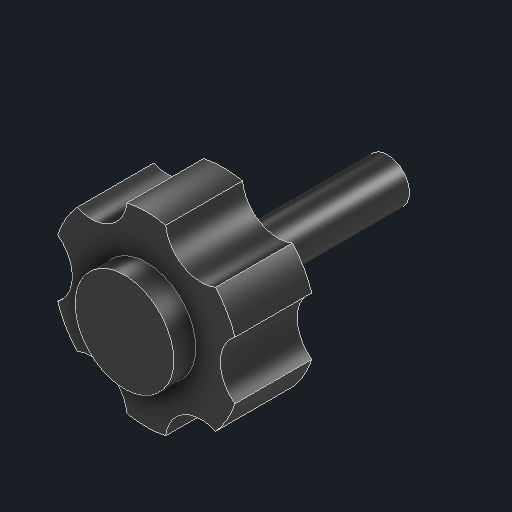
# Autodesk Inventor part: saddle_star_knob
Saved by Autodesk Inventor 2027.1 (Build 311270010, 270A)
## iProperties
Created: 2026-11-04
Part Number: saddle_star_knob
Material: Generic
Description: Saddle clamp knob
Document SubType Name: Modeling
Designer: Claude (from photos)
Density: 1 g/cm^3
Appearance: Glossy - Black
Author: alexg
Autodesk Inventor part; units mm, degrees
ref_plane "Work Plane1" through (0, 0, -18) normal (0, 0, 1) x (1, 0, 0)
sketch "Clamp screw sketch" plane through (0, 0, -18) normal (0, 0, 1) x (1, 0, 0)
  circle A0 centre (0, 0) radius 4
  constraints: 1 centre point
extrude "Clamp screw" add sketch "Clamp screw sketch" along normal blind 32
ref_plane "Work Plane2" through (0, 0, 12) normal (0, 0, 1) x (1, 0, 0)
sketch "Star body sketch" plane through (0, 0, 12) normal (0, 0, 1) x (1, 0, 0)
  circle A0 centre (0, 0) radius 17
  constraints: 1 centre point
extrude "Star body" add sketch "Star body sketch" along normal blind 14
ref_plane "Work Plane3" through (0, 0, 26) normal (0, 0, 1) x (1, 0, 0)
sketch "Lobes sketch" plane through (0, 0, 26) normal (0, 0, 1) x (1, 0, 0)
  circle A0 centre (20, 0) radius 6.5
  circle A1 centre (10, 17.3205) radius 6.5
  circle A2 centre (-10, 17.3205) radius 6.5
  circle A3 centre (-20, 0) radius 6.5
  circle A4 centre (-10, -17.3205) radius 6.5
  circle A5 centre (10, -17.3205) radius 6.5
  constraints: 6 centre point
extrude "Lobes" cut sketch "Lobes sketch" against normal blind 14
ref_plane "Work Plane4" through (0, 0, 26) normal (0, 0, 1) x (1, 0, 0)
sketch "Hub sketch" plane through (0, 0, 26) normal (0, 0, 1) x (1, 0, 0)
  circle A0 centre (0, 0) radius 9
  constraints: 1 centre point
extrude "Hub" add sketch "Hub sketch" along normal blind 4
body "Solid1"
